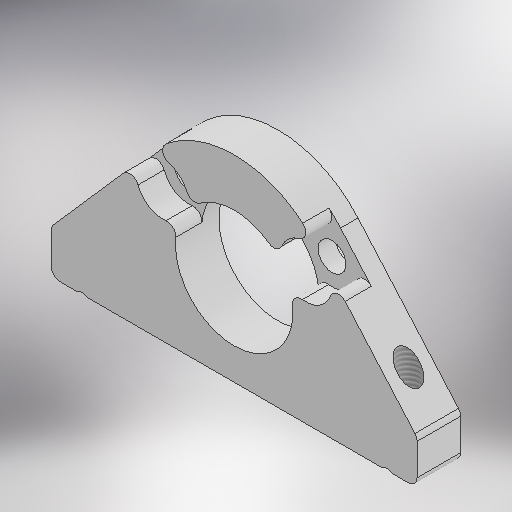
# Autodesk Inventor part: AP5.0_robomaster-fix
Saved by Autodesk Inventor 2025.3 (Build 293356030, 356C)
## iProperties
Created: 2026-09-02
Part Number: AP5.0_robomaster-fix
Material: 一般
Document SubType Name: Sheet Metal
Designer: ibuki_ono
Density: 1 g/cm^3
Sheet Metal Rule: Default_mm
Appearance: 既定
Author: ibuki_ono
Autodesk Inventor part; units mm, degrees
ref_plane "YZ Plane" through (0, 0, 0) normal (1, 0, 0) x (0, 1, 0)
ref_plane "XZ Plane" through (0, 0, 0) normal (0, 1, 0) x (-1, 0, 0)
ref_plane "XY Plane" through (0, 0, 0) normal (0, 0, 1) x (1, 0, 0)
sketch "スケッチ1" plane through (0, 0, 0) normal (0, 0, 1) x (1, 0, 0)
  circle A0 centre (0, 10.37) radius 12.25
  line L0 (-21, 0) -> (21, 0)
  line L1 (21, 0) -> (21, 5)
  line L2 (21, 5) -> (-21, 5)
  line L3 (-21, 5) -> (-21, 0)
  line L4 (-21, 5) -> (-9.211, 18.4459)
  line L5 (21, 5) -> (9.211, 18.4459)
  point P0 (0, 0)
  point P1 (0, 0)
  dimension "d0" = 24.5
  dimension "d1" = 10.37
  dimension "d2" = 42
  dimension "d3" = 5
  measures "d0" diameter of A0
  measures "d1" distance of point (0, 0) A0.centre
  measures "d2" distance of L2.end L1.end
  measures "d3" distance of L1.end L0.end
extrude "プレート1" add sketch "スケッチ1" along normal blind 5 contours A0 L2 | A0 L5 L2 | L2 L1 L0 A0 | A0 L0 L2 | A0 L2 L4 | A0 L0 L3 L2
sketch "スケッチ2" plane through (0, 0, 5) normal (0, 0, 1) x (1, 0, 0)
  arc A0 (9.211, 18.4459) -> (-9.211, 18.4459) centre (0, 10.37) ccw projected
  circle A1 centre (0, 10.37) radius 6.75
  point P0 (0, 0)
  dimension "d5" = 13.5
  constraints: 1 centre point, 1 coincident
  measures "d5" diameter of A1
extrude "押し出し1" cut sketch "スケッチ2" against normal through all
sketch "スケッチ3" plane through (0, 0, 5) normal (0, 0, 1) x (1, 0, 0)
  circle A0 centre (0, 10.37) radius 6.75 projected
  circle A1 centre (0, 10.37) radius 9.5 construction
  line L0 (0, 10.37) -> (8.2272, 15.12) construction
  line L1 (0, 10.37) -> (9.5, 10.37) construction
  line L2 (0, 10.37) -> (-8.2272, 15.12) construction
  line L3 (0, 10.37) -> (9.5, 10.37) construction
  point P0 (0, 0)
  dimension "d8" = 19
  dimension "d9" = 30
  dimension "d10" = 150
  constraints: 8 end point, 3 coincident, 2 equal length, 2 horizontal, 2 point on circle, 1 centre point
  measures "d8" diameter of A1
  measures "d9" angle of L1 L0
  measures "d10" angle of L3 L2
hole "穴1" at (-8.2272, 15.12, 5) at (8.2272, 15.12, 5) direction (0, 0, -1) diameter 3.2 end through all counterbore diameter 6 counterbore depth 3
fillet "フィレット1" radius 1 8 edges at (-6.284, 12.8344, 3.5) (-5.2763, 14.58, 3.5) (6.284, 12.8344, 3.5) (5.2763, 14.58, 3.5) (10.0144, 17.5296, 3.5) (10.8498, 16.5767, 3.5) (-10.0144, 17.5296, 3.5) (-10.8498, 16.5767, 3.5)
sketch "スケッチ4" plane through (0, 0, 5) normal (0, 0, 1) x (1, 0, 0)
  line L0 (21, 0) -> (-21, 0) projected
  circle A0 centre (-17.5, -0.85) radius 1.05
  circle A1 centre (17.5, -0.85) radius 1.05
  point P0 (0, 0)
  point P1 (0, 0)
  point P2 (0, 0)
  point P3 (16.8836, 0)
  point P4 (18.1164, 0)
  point P5 (-18.1164, 0)
  point P6 (-16.8836, 0)
  dimension "d19" = 2.1
  dimension "d20" = 2.1
  dimension "d21" = 0.85
  dimension "d22" = 0.85
  dimension "d23" = 17.5
  dimension "d24" = 17.5
  constraints: 2 centre point, 2 midpoint
  measures "d19" diameter of A0
  measures "d20" diameter of A1
  measures "d21" distance from line of L0 A0.centre
  measures "d22" distance from line of L0 A1.centre
  measures "d23" horizontal distance of point (0, 0) A1.centre
  measures "d24" horizontal distance of A0.centre point (0, 0)
extrude "押し出し2" cut sketch "スケッチ4" against normal through all contours L0 A1 | L0 A0 picked at (17.3578, 0.0365) picked at (-17.6422, 0.0365)
sketch "スケッチ5" plane through (-16.8836, 0, 0) normal (0, -1, 0) x (1, 0, 0)
  line L0 (0, 0) -> (-1.2329, 0) projected
  line L1 (0, 5) -> (0, 0) projected
  line L2 (-1.2329, 5) -> (0, 5) projected
  line L3 (-1.2329, 0) -> (-1.2329, 5) projected
  line L4 (-1.2329, 0) -> (-1.2329, 5) construction
  line L5 (-1.2329, 2.5) -> (0, 2.5) construction
  point P0 (16.8836, 0)
  point P1 (-0.6164, 2.5)
  constraints: 3 midpoint, 2 end point
hole "穴2" at (-17.5, 0, 2.5) direction (0, 1, 0) diameter 2.5 end through all
thread "ねじ1" size "M3x0.5" class "6H" standard "ISO Metric profile" full length
mirror "ミラー1" about plane through (0, 0, 0) normal (1, 0, 0) of "穴2"
fillet "フィレット2" radius 1 4 edges at (-21, 0, 2.5) (-21, 5, 2.5) (21, 0, 2.5) (21, 5, 2.5)
equation "\"d16\" = Thickness"
equation "\"d4\" = Thickness"
equation "\"d24\" = d23"
equation "\"BendRadius\" = Thickness"
equation "\"BendReliefWidth\" = Thickness"
equation "\"BendReliefDepth\" = 0.5 * Thickness"
equation "\"TransitionRadius\" = BendRadius"
equation "\"JacobiRadiusSize\" = BendRadius"
equation "\"GapSize\" = Thickness"
equation "\"Thickness\" = 5"
